hand (Autodesk Fusion 360 design; units mm, degrees)
Autodesk Fusion 360 part; units mm, degrees
sketch "스케치1" plane through (0, 0, 0) normal (0, 0, 1) x (1, 0, 0)
  line L0 (0, 0) -> (6, 0)
  line L1 (6, 0) -> (6, 30)
  line L2 (6, 30) -> (0, 30)
  line L3 (0, 30) -> (0, 0)
  circle A0 centre (21.25, 15) radius 21.25
  line L4 (0, 36.25) -> (21, 36.25)
  line L5 (21, 36.25) -> (21, -6.25)
  line L6 (21, -6.25) -> (0, -6.25)
  line L7 (0, -6.25) -> (0, 36.25)
  line L8 (0, 40.25) -> (21, 40.25)
  line L9 (21, 40.25) -> (21, -10.25)
  line L10 (21, -10.25) -> (0, -10.25)
  line L11 (0, -10.25) -> (0, 40.25)
  line L12 (0, 40.25) -> (-6, 40.25)
  line L13 (-6, 40.25) -> (-6, -10.25)
  line L14 (-6, -10.25) -> (0, -10.25)
  line L15 (0, -10.25) -> (0, 40.25)
  dimension "d1" = 6
  dimension "d2" = 30
  dimension "d3" = 42.5
  dimension "d4" = 15.25
  dimension "d5" = 15
  dimension "d6" = 21
  dimension "d7" = 4
  dimension "d8" = 4
  dimension "d9" = 6
  constraint horizontal L0
  constraint vertical L1
  constraint horizontal L2
  constraint vertical L3
  constraint coincident L0.start L3.end
  constraint horizontal L4
  constraint vertical L5
  constraint horizontal L6
  constraint vertical L7
  constraint tangent A0 L4
  constraint tangent A0 L6
  constraint horizontal L8
  constraint vertical L9
  constraint horizontal L10
  constraint vertical L11
  constraint horizontal L12
  constraint vertical L13
  constraint horizontal L14
  constraint vertical L15
  measures "d1" distance of L0.start L0.end
  measures "d2" distance of L0.start L2.end
  measures "d3" diameter of A0
  measures "d4" distance of L1 A0.centre
  measures "d5" distance of L2 A0.centre
  measures "d6" distance of L8.start L8.end
  measures "d7" distance of L4 L8
  measures "d8" distance of L6 L10
  measures "d9" distance of L8.start L12.end
extrude "돌출1" add sketch "스케치1" along normal blind 3 contours L0 L1 L3 A0 L7 L11 L15 | L3 L7 L11 L12 L13 L14 L15 | L0 L1 A0 L6 L7 L11 L15 | L1 L2 L3 A0 L7 L11 L15 | L6 L9 L10 L11 L15 | L1 L2 A0 L4 L7 L11 L15 | L4 L8 L9 L11 L15
